211403_P01_WALL-SKIN-BACK-UPPER-B3_CAD (Autodesk Fusion 360 design; units mm, degrees)
part number: 2026-11-02-00-08-38-498
description: WALL - SKIN - BACK UPPER - B3 | Vách hậu - tấm ốp alu trên trái | P01
part number: 211403
Autodesk Fusion 360 part; units mm, degrees
ref_plane "WorkPlane1" through (0, 0, 1233.13) normal (0, 0, 1) x (1, 0, 0) in component "211403 WALL - SKIN - BACK UPPER - B3"
sketch "SKETCH - SKIN PLATE" plane through (0, 0, 1233.13) normal (0, 0, 1) x (1, 0, 0) in component "211403 WALL - SKIN - BACK UPPER - B3"
  line L0 (-1201.74, 847) -> (-1.13, 847)
  line L1 (-1.13, 847) -> (-1.13, 850)
  line L2 (-1.13, 850) -> (-1201.74, 850)
  line L3 (-1201.74, 850) -> (-1201.74, 847)
  dimension "d162" = 1200.61
  dimension "d163" = 3
  dimension "d164" = 1201.74
  dimension "d165" = 847
  constraint horizontal L0
  constraint vertical L1
  constraint horizontal L2
  constraint vertical L3
  measures "d162" horizontal distance of L0.start L0.end
  measures "d163" vertical distance of L0.start L2.end
  measures "d164" horizontal distance of origin L0.start
  measures "d165" vertical distance of origin L0.start
extrude "EXTRUDE - SKIN PLATE" add sketch "SKETCH - SKIN PLATE" along normal blind 1118.61 in component "211403 WALL - SKIN - BACK UPPER - B3"
component "211403 WALL - SKIN - BACK UPPER - B3" placed x (1, 0, 0) y (0, 1, 0) z (0, 0, 1) at (0, 0, 0)
equation "pod_w_Ref = 2500 mm" comment "DECIDED: D-01; conventions s4 (X = +-1250)"
equation "pod_d_Ref = 1700 mm" comment "DECIDED: D-01; conventions s4 (Y = +-850)"
equation "pod_h_Ref = 2400 mm" comment "DECIDED: D-21 (room floor to roof skin top)"
equation "glide_h_Ref = 10 mm" comment "ASSUMPTION: layout study inputs.py glide_h"
equation "band_h_Ref = 100 mm" comment "SOURCE: layout study B1 list B-BAND 100x40; inputs.py base_h"
equation "outer_t_Ref = skin_t_Ref + bond_t_Ref + frame_t_Ref" comment "DECIDED: PM ruling 2026-10-31: ACP 3 + bond line 3 + frame 40, walls and ceiling (was 43)"
equation "cav_gap_Ref = 4 mm" comment "DECIDED: D-16, D-42: the gap between the outer panel and the lining cassette in the wall and ceiling stack"
equation "cass_t_Ref = 34 mm" comment "SOURCE: layout study B1 final list L-CASS 34 (tray + 25 gap + felt 9)"
equation "stack_t_Ref = outer_t_Ref + cav_gap_Ref + cass_t_Ref" comment "CALCULATION: D-16, D-42 stack, walls and ceiling: outer panel + cavity gap + cassette (PM ruling 2026-10-31 on outer_t)"
equation "lin_gap_Ref = 4 mm" comment "ASSUMPTION: PM ruling pass C: gap above the upper side linings so they stay floating (= the 4 mm stack gap)"
equation "seam_gap_Ref = 2.26 mm" comment "DECIDED: PM ruling 2026-10-31 (Mechanical Checker F-001, F-005): the Joints Engineer's 2.26 mm at all nine site seam types, set by a metal stop (1.5 stop washer + 0.76 rivnut head; joints register section 2.8)"
equation "wall_z0_Ref = glide_h_Ref + band_h_Ref" comment "CALCULATION: base band top: glides + band"
equation "panel_z0_Ref = wall_z0_Ref + seam_gap_Ref" comment "CALCULATION: walls stand one seam_gap above the band top (joints register 2.8, IF-01)"
equation "back_oh_Ref = pod_h_Ref - outer_t_Ref - seam_gap_Ref - panel_z0_Ref" comment "CALCULATION: PM ruling 2026-10-31 (pass D, F-004): the back outer frames run up to the ceiling frame (pod_h - outer_t), less the seam_gap under it, closing the slot at the back top edge"
equation "back_ph_Ref = ( back_oh_Ref - seam_gap_Ref ) / 2" comment "CALCULATION: D-23: 4 sheets on the back, two equal rows with one seam_gap between them (joints register 2.8); the lower back linings match the lower row, as on the side walls"
equation "half_pw_Ref = ( pod_w_Ref - 2 * outer_t_Ref - 3 * seam_gap_Ref ) / 2" comment "CALCULATION: SKIN width of each back and ceiling panel: two skins and three seam_gap seams between the side frames (F-001, joints register 2.8)"
equation "n_base_bolt_Ref = 4" comment "DECIDED: PM ruling 2026-10-31, J-BASE-01: bolts per panel along the band, evenly spaced"
equation "skin_t_Ref = 3 mm" comment "DECIDED: ACP skin, walls and ceiling (D-16; PM ruling 2026-10-31 on outer_t)"
equation "bond_t_Ref = 3 mm" comment "DECIDED: bond line between the ACP and the frame (PM ruling 2026-10-31 on outer_t)"
equation "frame_t_Ref = 40 mm" comment "DECIDED: aluminium frame tube depth, walls and ceiling (PM ruling 2026-10-31 on outer_t)"
equation "close_gap_Ref = 5.5 mm" comment "DECIDED: PM ruling 2026-10-31 (joints register, F-011/F-012): frame gap at the closing seams B1-B2, B3-B4 and C1-C2, which have no hard stop (slotted holes, thicker gasket)"
equation "half_fw_Ref = ( pod_w_Ref - 2 * outer_t_Ref - 2 * seam_gap_Ref - close_gap_Ref ) / 2" comment "CALCULATION: FRAME width of each back and ceiling panel: the skins overhang their frames by half_pw - half_fw at the closing seam (PM ruling 2026-10-31)"
equation "bolt_edge_inset_Ref = 220 mm" comment "DECIDED: PM ruling 2026-10-31: on every bolted edge the end bolts sit this far in from each panel end (the FRAME end, where the bolts go), the rest evenly spaced"
equation "spigot_inset_Ref = 100 mm" comment "DECIDED: PM ruling 2026-10-31: locating spigots this far in from each panel end (round hole at one end, slot at the other)"
equation "pod_w = pod_w_Ref" comment "LINKED: pod_w_Ref, derived from 100000_P04_POD-SKELETON_CAD v6 (skeleton is the single source)"
equation "pod_d = pod_d_Ref" comment "LINKED: pod_d_Ref, derived from 100000_P04_POD-SKELETON_CAD v6 (skeleton is the single source)"
equation "pod_h = pod_h_Ref" comment "LINKED: pod_h_Ref, derived from 100000_P04_POD-SKELETON_CAD v6 (skeleton is the single source)"
equation "panel_z0 = panel_z0_Ref" comment "LINKED: panel_z0_Ref, derived from 100000_P04_POD-SKELETON_CAD v6 (skeleton is the single source)"
equation "back_ph = back_ph_Ref" comment "LINKED: back_ph_Ref, derived from 100000_P04_POD-SKELETON_CAD v6 (skeleton is the single source)"
equation "back_oh = back_oh_Ref" comment "LINKED: back_oh_Ref, derived from 100000_P04_POD-SKELETON_CAD v6 (skeleton is the single source)"
equation "half_pw = half_pw_Ref" comment "LINKED: half_pw_Ref, derived from 100000_P04_POD-SKELETON_CAD v6 (skeleton is the single source)"
equation "half_fw = half_fw_Ref" comment "LINKED: half_fw_Ref, derived from 100000_P04_POD-SKELETON_CAD v6 (skeleton is the single source)"
equation "close_gap = close_gap_Ref" comment "LINKED: close_gap_Ref, derived from 100000_P04_POD-SKELETON_CAD v6 (skeleton is the single source)"
equation "stack_t = stack_t_Ref" comment "LINKED: stack_t_Ref, derived from 100000_P04_POD-SKELETON_CAD v6 (skeleton is the single source)"
equation "outer_t = outer_t_Ref" comment "LINKED: outer_t_Ref, derived from 100000_P04_POD-SKELETON_CAD v6 (skeleton is the single source)"
equation "cass_t = cass_t_Ref" comment "LINKED: cass_t_Ref, derived from 100000_P04_POD-SKELETON_CAD v6 (skeleton is the single source)"
equation "lin_gap = lin_gap_Ref" comment "LINKED: lin_gap_Ref, derived from 100000_P04_POD-SKELETON_CAD v6 (skeleton is the single source)"
equation "seam_gap = seam_gap_Ref" comment "LINKED: seam_gap_Ref, derived from 100000_P04_POD-SKELETON_CAD v6 (skeleton is the single source)"
equation "skin_t = skin_t_Ref" comment "LINKED: skin_t_Ref, derived from 100000_P04_POD-SKELETON_CAD v6 (skeleton is the single source)"
equation "bond_t = bond_t_Ref" comment "LINKED: bond_t_Ref, derived from 100000_P04_POD-SKELETON_CAD v6 (skeleton is the single source)"
equation "bolt_edge_inset = bolt_edge_inset_Ref" comment "LINKED: bolt_edge_inset_Ref, derived from 100000_P04_POD-SKELETON_CAD v6 (skeleton is the single source)"
equation "spigot_inset = spigot_inset_Ref" comment "LINKED: spigot_inset_Ref, derived from 100000_P04_POD-SKELETON_CAD v6 (skeleton is the single source)"
equation "n_base_bolt = n_base_bolt_Ref" comment "LINKED: n_base_bolt_Ref, derived from 100000_P04_POD-SKELETON_CAD v6 (skeleton is the single source)"
equation "tube_w = 20 mm" comment "CONFIRMED: D-34, D-54, kept by D-131 (the same outside sections in welded, galvanized steel box tube): 20 x 40; the 20 mm face carries the skin, so the 40 mm runs through the wall (outer_t = ACP 3 + frame 40)"
equation "tube_d = outer_t - skin_t - bond_t" comment "CALCULATION: frame depth = outer panel 46 - skin 3 - bond 3 = 40 (D-34)"
equation "stud_t = 0.8 mm" comment "SOURCE: the same: the studs at 0.8 (no rivnut, only the skin's bond line)"
equation "plate_t = 2 mm" comment "SOURCE: the Joints Engineer's corner detail (2026-11-01 05:05): a 2 mm steel plate welded into each mitre, the members cut back so it fits, centred on the old mitre line"
equation "stile_pitch_max = 300 mm" comment "CONFIRMED: PM ruling 2026-11-01 (D-131 sample): the ACP flexes 2 mm or less under a 100 N push at a bay's centre, edges simply supported (make_acp_spans.py), so members about 300 apart; it was 400 (D-16, D-34)"
equation "skin_setback = 0 mm" comment "ASSUMPTION: skin edge set back from the frame's top and bottom edges: 0, so the outside reveal equals the 2.26 seam gap (D-23: crisp, aligned reveals; joints register 2.8 leaves the setback to the WALL drawing)"
equation "fill_t = tube_d" comment "CALCULATION: 40 mm PET fill fills the frame depth (D-34; layout study 40 mm)"
equation "bolt_d = 7 mm" comment "CONFIRMED: PM ruling on F-009: bolt holes 7.0 (0.51 float), position tolerance 0.4 (+-0.2) from the spigot hole, CNC or drill jig (joints register FR-02)"
equation "access_d = 19 mm" comment "CALCULATION: register FR-03: passes the 18 mm head washer (ISO 7093-1, R-J10), the M6 head and the 5 mm key; holds the grommet retainer (H-02)"
equation "bolt_line_y = pod_d / 2 - skin_t - bond_t - tube_d / 2" comment "CONFIRMED: J-WALL-02 bolt line on the back panel's tube centre, Y 824 (joints register R-J15, FR-07)"
equation "rivnut_d = 10 mm" comment "CONFIRMED: D-163 (the Lead's ruling, 2026-11-01): Sherex CAL2-610-4.2 in a round drilled hole Ø10.00 +0.10/0, inside the maker's 10.00 +0.15/-0.0 (Sherex drawing CAL2-610-4.2 rev B, note 2) so the bolt-hole stack ST-03 stays positive; T06's spin-out test confirms it"
equation "spigot_d = 8.5 mm" comment "ASSUMPTION: register FR-05: hole for the 8 mm locating spigot H-05"
equation "spigot_edge = spigot_inset" comment "CALCULATION: the skeleton's spigot_inset: spigots 100 from each end of the edge (PM ruling 2026-10-31, R-J13)"
equation "bolt_edge = bolt_edge_inset" comment "CALCULATION: the skeleton's bolt_edge_inset: end bolts 220 in from the panel's ends, evenly spaced, every bolt 30 or more from any stile (PM ruling 2026-10-31, R-J14)"
equation "pocket_w = 60 mm" comment "ASSUMPTION: register FR-10: fill left out 60 x 60 next to each bolt for the key"
equation "felt_t = 9 mm" comment "SOURCE: plan VT03-PET 9 mm PET felt; HW-SEL A3; D-31 (the factory's felt)"
equation "tray_t = 0.5 mm" comment "CONFIRMED: D-37: galvanised steel tray 0.5 mm"
equation "tray_h = cass_t" comment "CONFIRMED: PM ruling 2026-10-31 (WALL group, option 1): the wall cassettes use the ceiling's tray, returns the full cassette depth (34) turned in as lips that hold the felt, no ribs; settles H09 for the walls"
equation "lip_w = 12 mm" comment "CONFIRMED: PM ruling 2026-10-31 (WALL group, option 1): 12 mm lips hold the felt edge"
equation "bend_r = tray_t" comment "ASSUMPTION: inside bend radius 1 x t for 0.5 mm DX51D (the sheet metal rule's bend radius is its Thickness); the factory's tooling sets it (guideline 9)"
equation "felt_c = 1 mm" comment "ASSUMPTION: felt edge clearance inside the returns, as the ceiling cassette"
equation "gap_h = tray_h - felt_t - 2 * tray_t" comment "CALCULATION: air gap between the tray base and the felt (24): the acoustic gap (D-17) and the cable path (D-26)"
equation "clip_zone_h = 60 mm" comment "ASSUMPTION: height of each reserved clip zone (H03: no clip named)"
equation "clip_zone_dz = 100 mm" comment "ASSUMPTION: clip zone centre from the cassette's top and bottom edges (H03)"
equation "stopw_od = 20 mm" comment "SOURCE: joints register H-08: stop washer Ø10.5 x Ø20 x 1.5 (PROPOSED part)"
equation "stopw_id = 10.5 mm" comment "SOURCE: joints register H-08"
equation "stopw_t = 1.5 mm" comment "SOURCE: joints register H-08: rivnut head 0.76 + washer 1.5 = the 2.26 stop (R-J5)"
equation "rivnut_head_d = 12.95 mm" comment "SOURCE: Sherex CAL2-610-4.2 rev B: flange Ø12.45 to 12.95, the largest modelled (D-163)"
equation "rivnut_head_t = 0.76 mm" comment "SOURCE: Sherex CAL2-610-4.2 rev B: flange 0.68 to 0.84, its middle; with the 1.5 stop washer the 2.26 stop (R-J5), as before (D-163)"
equation "rivnut_body_d = 9.91 mm" comment "SOURCE: Sherex CAL2-610-4.2 rev B: knurled body Ø9.91 max (D-163)"
equation "rivnut_len = 9.65 mm" comment "SOURCE: Sherex CAL2-610-4.2 rev B, note 3: installed length 9.65 max under the flange (14.35 to 15.11 before setting); the bulge inside the tube is not modelled (D-163)"
equation "m6_d = 6 mm" comment "CALCULATION: M6 threads shown at their 6 mm major diameter (no modelled thread)"
equation "spigot_pin_d = 8 mm" comment "SOURCE: joints register H-05: Ø8 stainless pin; the part itself is Joints' 831001 STEP, placed as it is (F-189)"
equation "spigot_proud = 8 mm" comment "SOURCE: joints register H-05 and Joints' README: the pin's top 8.00 above the tube face (Z 7.24 above its origin on the rivnut head)"
equation "spigot_slot = 14 mm" comment "ASSUMPTION: register FR-05: the back panels' slot for the second spigot (D-167 lengthens the side panels' only)"
equation "tube_t = 1.0 mm" comment "SOURCE: the Joints Engineer's gauges for D-131 (2026-11-01): a back panel's perimeter members (rails, outer and centre stiles) at 1.0; the studs 0.8"
equation "lead_in = 1 mm" comment "SOURCE: joints register 2.10 (R-J9): 1 x 45 degree lead-in on the top edge of each closing-seam face, so the panel beside it drops in past it without catching the bulb seal"
equation "pnl_len = half_pw" comment "CALCULATION: skeleton half_pw: the back panel's skin width (1200.61 on P04)"
equation "frm_len = half_fw" comment "CALCULATION: the skeleton's half_fw, 1198.99: the frame stops close_gap / 2 from X 0 and 1.62 short of its skin (R-J16)"
equation "pnl_h = back_oh - back_ph - seam_gap" comment "CALCULATION: skeleton back row height (1118.61 on P04)"
equation "frm_h = pnl_h" comment "CALCULATION: the frame fills the row height; the seam gaps are outside it (P04)"
equation "top_h = tube_w" comment "CALCULATION: the back panels' top rails stay 20 x 40 (the ceiling's back member is the 40 x 40, R-J3)"
equation "stile_n_mid = 3" comment "CALCULATION: PM ruling 2026-11-01 (D-135): 3 studs on a back panel, so the skin flexes 1.99 mm under a 100 N push at 274.75 clear (make_acp_spans.py); a fixed count (the studs are copies held by joints), the pitch follows the width, and the build refuses a pitch over stile_pitch_max"
equation "stile_pitch = ( frm_len - tube_w ) / ( stile_n_mid + 1 )" comment "CALCULATION: equal stile pitch, centre to centre"
equation "stile_len = frm_h - 2 * tube_w" comment "CALCULATION: studs between the rails (square ends, welded T joints, D-131); the perimeter stiles run the full height, mitred (D-117) and welded"
equation "n_len_bolt = n_base_bolt" comment "CALCULATION: the skeleton's n_base_bolt (4): also on the horizontal seam and the ceiling back edge (register 2.9; the skeleton's n_ceil_back_bolt 3 is an old assumption, flagged)"
equation "len_bolt_pitch = ( frm_len - 2 * bolt_edge ) / ( n_len_bolt - 1 )" comment "CALCULATION: 253.00 on P04: 220, 473.00, 725.99, 978.99 from the frame's ends (register 2.9; the skeleton's back_base_pitch uses the 1200.61 skin and gives 253.54, flagged to its owner)"
equation "n_side_jnt = 3" comment "SOURCE: 3 bolts on the back corner and on the closing seam (register 2.9)"
equation "side_jnt_pitch = ( pnl_h - 2 * bolt_edge ) / ( n_side_jnt - 1 )" comment "CALCULATION: 339.31 on P04: 220, 559.31, 898.61 up the 1118.61 edge (register 2.9)"
equation "cass_len = pod_w / 2 - stack_t - seam_gap / 2" comment "ASSUMPTION: PROPOSED (WALL): from the side lining's face to seam_gap / 2 short of X 0. Each cassette hangs on its own panel's frame and the closing seam moves (5.2 to 5.8, register 2.11), so the skeleton's touching edges at X 0 could clash; a 2.26 gap matches the skin seam above it (R-J16) and takes the H-14 edge seal"
equation "cass_h = pod_h - outer_t - lin_gap - ( panel_z0 + back_ph + seam_gap )" comment "CALCULATION: lower: the row height; upper: up to lin_gap under the ceiling frame, floating (D-57; P04)"
equation "d160 = ( panel_z0 + back_ph + seam_gap ) + skin_setback"
equation "d162 = ( -seam_gap / 2 ) - ( -seam_gap / 2 - half_pw )"
equation "d163 = ( pod_d / 2 ) - ( pod_d / 2 - skin_t )"
equation "d164 = abs(-seam_gap / 2 - half_pw)"
equation "d165 = abs(pod_d / 2 - skin_t)"
equation "d166 = ( ( panel_z0 + back_oh ) - skin_setback ) - ( ( panel_z0 + back_ph + seam_gap ) + skin_setback )"
named bodies: "SKIN - ACP 3, OVERHANGS THE FRAME 1.62 AT THE CLOSING SEAM"
